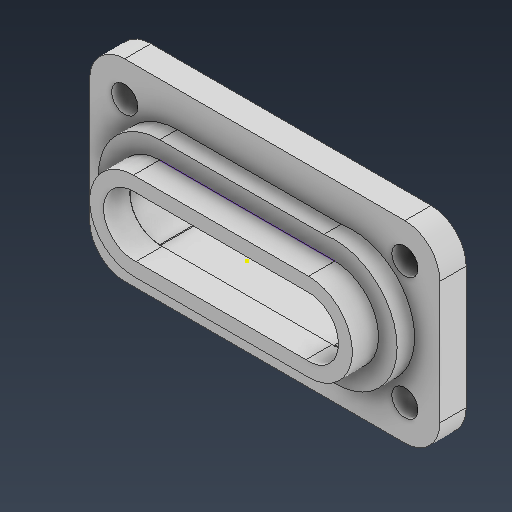
# Autodesk Inventor part: WorkSheet2
Saved by Autodesk Inventor 2026.4 (Build 304435000, 435)
## iProperties
Created: 2026-08-11
Part Number: WorkSheet2
Material: Generic
Document SubType Name: Modeling
Designer: crist
Density: 1 g/cm^3
Appearance: Default
Author: crist
Autodesk Inventor part; units mm, degrees
ref_plane "YZ Plane" through (0, 0, 0) normal (1, 0, 0) x (0, 1, 0)
ref_plane "XZ Plane" through (0, 0, 0) normal (0, 1, 0) x (-1, 0, 0)
ref_plane "XY Plane" through (0, 0, 0) normal (0, 0, 1) x (1, 0, 0)
sketch "Sketch1" plane through (0, 0, 0) normal (0, 0, 1) x (1, 0, 0)
  line L0 (-1270, 431.8) -> (1270, 431.8)
  line L1 (1270, -431.8) -> (-1270, -431.8)
  line L2 (1270, -635) -> (-1270, -635)
  line L3 (-1270, 635) -> (1270, 635)
  line L4 (1270, -889) -> (-1270, -889)
  line L5 (-1270, 889) -> (1270, 889)
  arc A0 (1232.2117, -431.8) -> (1232.2117, 431.8) centre (1270, 0) ccw
  arc A1 (1270, -634.4095) -> (1270, 634.4095) centre (1270, 0) ccw
  arc A2 (1270, -888.9325) -> (1270, 888.9325) centre (1270, 0) ccw
  line L6 (1270, 889) -> (1270, 888.9325)
  line L7 (1270, 635) -> (1270, 634.4095)
  line L8 (1270, 635) -> (1270, 634.4095)
  line L9 (1270, -888.9325) -> (1270, -889)
  line L10 (1270, -634.4095) -> (1270, -635)
  line L11 (1270, 433.4503) -> (1270, 431.8)
  line L12 (1270, -431.8) -> (1270, -433.4503)
  arc A3 (-1232.2117, 431.8) -> (-1232.2117, -431.8) centre (-1270, 0) ccw
  arc A4 (-1270, 634.4095) -> (-1270, -634.4095) centre (-1270, 0) ccw
  arc A5 (-1270, 888.9325) -> (-1270, -888.9325) centre (-1270, 0) ccw
  line L13 (-1270, 888.9325) -> (-1270, 889)
  line L14 (-1270, 634.4095) -> (-1270, 635)
  line L15 (-1270, 634.4095) -> (-1270, 635)
  line L16 (-1270, 431.8) -> (-1270, 433.4503)
  line L17 (-1270, 431.8) -> (-1270, 433.4503)
  line L18 (-1270, -433.4503) -> (-1270, -431.8)
  line L19 (-1270, -889) -> (-1270, -888.9325)
  line L20 (-1270, -635) -> (-1270, -634.4095)
  line L21 (-1270, -635) -> (-1270, -634.4095)
  line L22 (-1270, -433.4503) -> (-1270, -431.8)
  point P0 (0, 0)
  point P1 (-1232.2117, 431.8)
  point P2 (-1232.2117, -431.8)
  constraints: 46 end point, 37 parallel, 16 point on circle, 10 perpendicular, 6 centre point, 4 coincident, 3 horizontal, 2 point on line
sketch "Sketch2" plane through (0, 0, 0) normal (0, 0, 1) x (1, 0, 0)
  line L0 (-2032, -1397) -> (2032, -1397)
  line L1 (2032, 1397) -> (-2032, 1397)
  line L2 (-2540, -889) -> (-2540, 889)
  line L3 (2540, 889) -> (2540, -889)
  arc A0 (2540, 889) -> (2032, 1397) centre (2032, 889) ccw
  arc A1 (2032, -1397) -> (2540, -889) centre (2032, -889) ccw
  arc A2 (-2032, 1397) -> (-2540, 889) centre (-2032, 889) ccw
  arc A3 (-2540, -889) -> (-2032, -1397) centre (-2032, -889) ccw
  circle A4 centre (-2032, 889) radius 190.5
  circle A5 centre (-2032, -889) radius 190.5
  circle A6 centre (2032, 889) radius 190.5
  circle A7 centre (2032, -889) radius 190.5
  line L4 (-1270, -431.8) -> (1270, -431.8)
  line L5 (1270, 431.8) -> (-1270, 431.8)
  arc A8 (-1210.3843, 431.8) -> (-1210.3843, -431.8) centre (-1270, 0) ccw
  arc A9 (1205.3721, -431.8) -> (1205.3721, 431.8) centre (1270, 0) ccw
  point P0 (0, 0)
  constraints: 12 end point, 12 point on circle, 10 centre point, 4 point on line, 4 tangent, 3 parallel, 2 horizontal, 1 coincident
extrude "Extrusion1" add sketch "Sketch2" against normal blind 381 contours A3 L2 A2 L1 A0 L3 A1 L0 | A8 L5 A9 L4
extrude "Extrusion2" add sketch "Sketch1" along normal blind 635 contours L2 L20 A4 L14 L3 L7 A1 L10
sketch "Sketch3" plane through (0, 0, 0) normal (0, 0, 1) x (1, 0, 0)
  line L0 (-1270, -889) -> (1270, -889)
  line L1 (1270, 889) -> (-1270, 889)
  arc A0 (-1270, 889) -> (-1270, -889) centre (-1270, 0) ccw
  arc A1 (1109.6541, -889) -> (1109.6541, 889) centre (1270, 0) ccw
  point P0 (0, 0)
  constraints: 4 end point, 4 point on circle, 2 centre point, 2 point on line, 1 horizontal, 1 parallel, 1 tangent
extrude "Extrusion3" add sketch "Sketch3" along normal blind 254
sketch "Sketch4" plane through (0, 0, 254) normal (0, 0, 1) x (1, 0, 0)
  line L0 (1270, -635) -> (-1270, -635)
  line L1 (-1270, 635) -> (1270, 635)
  point P0 (0, 0)
  constraints: 4 end point, 1 horizontal, 1 parallel
sketch "Sketch5" plane through (0, 0, 254) normal (0, 0, 1) x (1, 0, 0)
  line L0 (1270, -444.5) -> (-1270, -444.5)
  line L1 (-1270, 444.5) -> (1270, 444.5)
  arc A0 (-1214.7573, 425.1651) -> (-1214.7573, -425.1651) centre (-1270, 0) ccw
  arc A1 (1270, -417.6062) -> (1270, 417.6062) centre (1270, 0) ccw
  line L2 (-1270, -444.5) -> (-1270, -428.7389)
  line L3 (-1270, 428.7389) -> (-1270, 444.5)
  line L4 (-1048.0489, 366.8171) -> (-1270, 444.5) construction
  line L5 (-1270, -444.5) -> (-1048.0489, -366.8171) construction
  line L6 (1270, 444.5) -> (1270, 417.6062)
  line L7 (1270, -417.6062) -> (1270, -444.5)
  point P0 (0, 0)
  constraints: 16 end point, 6 point on circle, 5 parallel, 2 centre point, 2 perpendicular, 2 point on line, 1 horizontal
extrude "Extrusion4" cut sketch "Sketch5" against normal blind 1270
body "Solid1"
